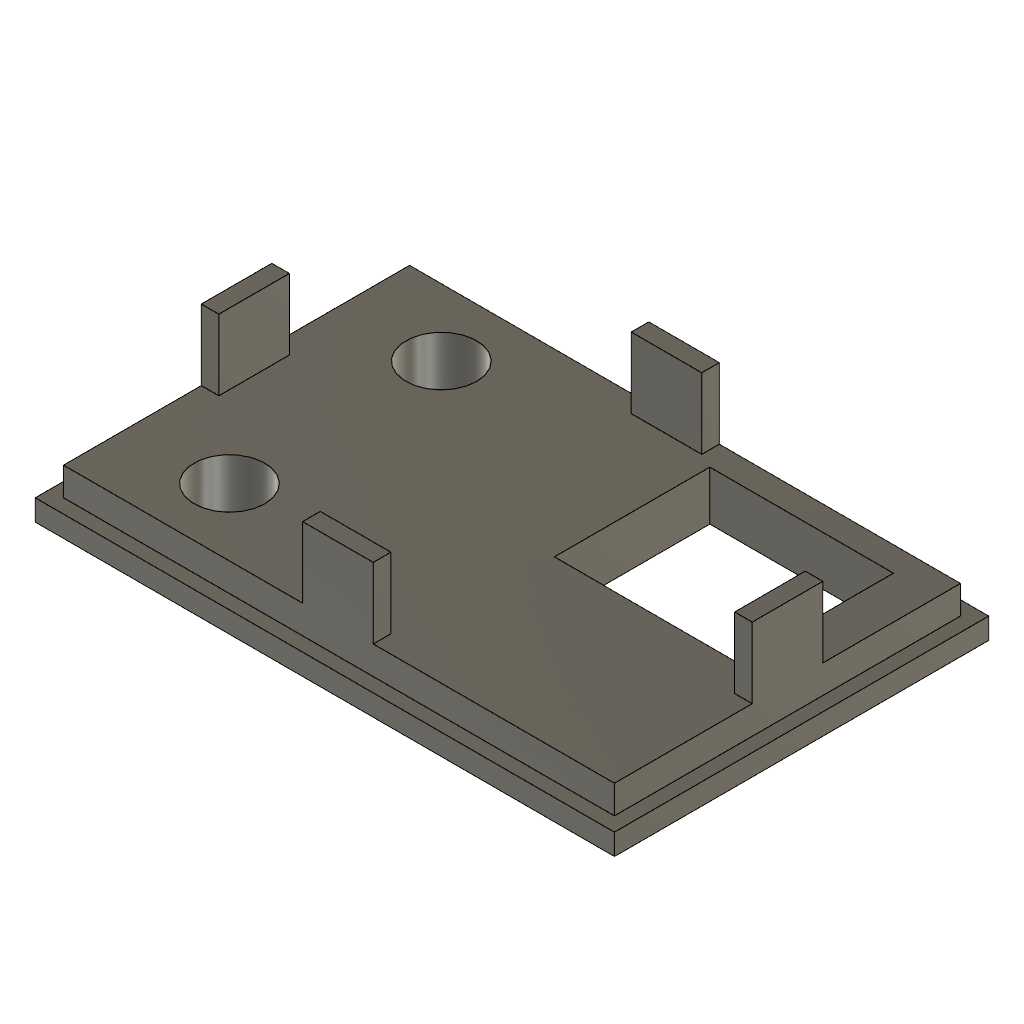
LID_CONVEYOR (Autodesk Fusion 360 design; units mm, degrees)
part number: 2026-11-19-21-15-40-703
Autodesk Fusion 360 part; units mm, degrees
sketch "Sketch1" plane through (0, 0, 0) normal (0, 0, 1) x (1, 0, 0)
  line L0 (41, 26.5) -> (-41, 26.5)
  line L1 (-41, 26.5) -> (-41, -26.5)
  line L2 (-41, -26.5) -> (41, -26.5)
  line L3 (41, -26.5) -> (41, 26.5)
  line L4 (41, 26.5) -> (-41, -26.5) construction
  line L5 (-41, 26.5) -> (41, -26.5) construction
  dimension "d1" = 82
  dimension "d2" = 53
  constraint horizontal L0
  constraint perpendicular L0 L1
  constraint parallel L0 L2
  constraint parallel L1 L3
  constraint coincident L4 origin
  constraint coincident L5 origin
  measures "d1" distance of L1.end L2.end
  measures "d2" distance of L0.end L1.end
extrude "Extrude1" add sketch "Sketch1" along normal blind 3
sketch "Sketch2" plane through (0, 0, 3) normal (0, 0, 1) x (-1, 0, 0)
  line L0 (-41, 26.5) -> (-41, -26.5)
  line L1 (-41, -26.5) -> (41, -26.5)
  line L2 (41, -26.5) -> (41, 26.5)
  line L3 (41, 26.5) -> (-41, 26.5)
  line L4 (-39, -24.5) -> (39, -24.5)
  line L5 (39, -24.5) -> (39, 24.5)
  line L6 (39, 24.5) -> (-39, 24.5)
  line L7 (-39, 24.5) -> (-39, -24.5)
  line L8 (-39, -24.5) -> (39, 24.5) construction
  line L9 (39, -24.5) -> (-39, 24.5) construction
  dimension "d5" = 78
  dimension "d6" = 49
  constraint horizontal L4
  constraint perpendicular L4 L5
  constraint parallel L4 L6
  constraint parallel L5 L7
  constraint coincident L8 origin
  constraint coincident L9 origin
  measures "d5" distance of L5.end L6.end
  measures "d6" distance of L4.end L5.end
extrude "Extrude2" add sketch "Sketch2" along normal blind 4 contours L4 L5 L6 L7
sketch "Sketch3" plane through (0, 0, 7) normal (0, 0, 1) x (-1, 0, 0)
  line L0 (-39, 24.5) -> (-39, -24.5)
  line L1 (-39, -24.5) -> (39, -24.5)
  line L2 (39, -24.5) -> (39, 24.5)
  line L3 (39, 24.5) -> (-39, 24.5)
  line L4 (-7, 1) -> (-33, 1)
  line L5 (-33, 1) -> (-33, -21)
  line L6 (-33, -21) -> (-7, -21)
  line L7 (-7, -21) -> (-7, 1)
  line L8 (-7, 1) -> (-33, -21) construction
  line L9 (-33, 1) -> (-7, -21) construction
  point P0 (-20, -10)
  dimension "d9" = 26
  dimension "d10" = 22
  constraint horizontal L4
  constraint perpendicular L4 L5
  constraint parallel L4 L6
  constraint parallel L5 L7
  constraint coincident L8 P0
  constraint coincident L9 P0
  measures "d9" distance of L5.end L6.end
  measures "d10" distance of L4.end L5.end
extrude "Extrude3" cut sketch "Sketch3" against normal blind 7 contours L4 L5 L6 L7
sketch "Sketch4" plane through (0, 0, 7) normal (0, 0, 1) x (-1, 0, 0)
  line L0 (-33, 1) -> (-7, 1)
  line L1 (-7, 1) -> (-7, -21)
  line L2 (-7, -21) -> (-33, -21)
  line L3 (-33, -21) -> (-33, 1)
  line L4 (-39, 24.5) -> (-39, -24.5)
  line L5 (-39, -24.5) -> (39, -24.5)
  line L6 (39, -24.5) -> (39, 24.5)
  line L7 (39, 24.5) -> (-39, 24.5)
  circle A0 centre (25, -15) radius 5
  circle A1 centre (25, 15) radius 5
  dimension "d13" = 10
  dimension "d14" = 10
  measures "d13" diameter of A0
  measures "d14" diameter of A1
extrude "Extrude4" cut sketch "Sketch4" against normal blind 7 contours A0 | A1
sketch "Sketch5" plane through (0, 0, 7) normal (0, 0, 1) x (-1, 0, 0)
  circle A0 centre (25, -15) radius 5
  circle A1 centre (25, 15) radius 5
  line L0 (-33, 1) -> (-7, 1)
  line L1 (-7, 1) -> (-7, -21)
  line L2 (-7, -21) -> (-33, -21)
  line L3 (-33, -21) -> (-33, 1)
  line L4 (-39, 24.5) -> (-39, -24.5)
  line L5 (-39, -24.5) -> (39, -24.5)
  line L6 (39, -24.5) -> (39, 24.5)
  line L7 (39, 24.5) -> (-39, 24.5)
  line L8 (-4.8605, 24.5) -> (5.1395, 24.5)
  line L9 (5.1395, 24.5) -> (5.1395, 22)
  line L10 (5.1395, 22) -> (-4.8605, 22)
  line L11 (-4.8605, 22) -> (-4.8605, 24.5)
  line L12 (-4.8605, -24.5) -> (5.1395, -24.5)
  line L13 (5.1395, -24.5) -> (5.1395, -22)
  line L14 (5.1395, -22) -> (-4.8605, -22)
  line L15 (-4.8605, -22) -> (-4.8605, -24.5)
  line L16 (-39, 5) -> (-36.5, 5)
  line L17 (-36.5, 5) -> (-36.5, -5)
  line L18 (-36.5, -5) -> (-39, -5)
  line L19 (-39, -5) -> (-39, 5)
  line L20 (39, 5) -> (36.5, 5)
  line L21 (36.5, 5) -> (36.5, -5)
  line L22 (36.5, -5) -> (39, -5)
  line L23 (39, -5) -> (39, 5)
  dimension "d17" = 10
  dimension "d18" = 2.5
  dimension "d19" = 10
  dimension "d20" = 2.5
  dimension "d21" = 2.5
  dimension "d22" = 2.5
  constraint horizontal L8
  constraint vertical L9
  constraint horizontal L10
  constraint vertical L11
  constraint coincident L7 L8.start
  constraint horizontal L12
  constraint vertical L13
  constraint horizontal L14
  constraint vertical L15
  constraint coincident L5 L12.start
  constraint horizontal L16
  constraint vertical L17
  constraint horizontal L18
  constraint vertical L19
  constraint coincident L4 L16.start
  constraint horizontal L20
  constraint vertical L21
  constraint horizontal L22
  constraint vertical L23
  constraint coincident L6 L20.start
  measures "d17" distance of L8.start L8.end
  measures "d18" distance of L8.start L10.end
  measures "d19" distance of L12.start L12.end
  measures "d20" distance of L12.start L14.end
  measures "d21" distance of L16.start L16.end
  measures "d22" distance of L20.start L20.end
extrude "Extrude5" add sketch "Sketch5" along normal blind 10 contours L4 L16 L17 L18 L19 | L7 L8 L9 L10 L11 | L5 L12 L13 L14 L15 | L6 L20 L21 L22 L23
